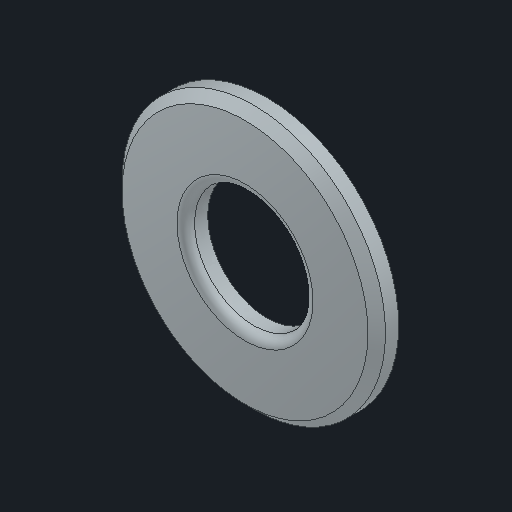
# Autodesk Inventor part: Arruela Lisa DIN 125 - B2,5 - 300 HV
Saved by Autodesk Inventor 2026.1 (Build 301233000, 233)
## iProperties
Created: 2025-07-13
Part Number: Arruela Lisa DIN 125 - B2,5 - 300 HV
Material: Aço, carbono
Document SubType Name: Modeling
Designer: Cliente
Mass: 0.0850199 g
Surface Area: 0.557927 cm^2
Volume: 0.0108306 cm^3
Density: 7.85 g/cm^3
Appearance: Zinco
Author: Cliente
Autodesk Inventor part; units mm, degrees
ref_plane "YZ Plane" through (0, 0, 0) normal (1, 0, 0) x (0, 1, 0)
ref_plane "XZ Plane" through (0, 0, 0) normal (0, 1, 0) x (-1, 0, 0)
ref_plane "XY Plane" through (0, 0, 0) normal (0, 0, 1) x (1, 0, 0)
sketch "Esboço1" plane through (0, 0, 0) normal (0, 1, 0) x (-1, 0, 0)
  line L0 (0, 0) -> (1.35, 0)
  line L1 (0, 1.0374) -> (0, 0)
  line L2 (1.35, 0) -> (1.35, 0.3)
  line L3 (0, 0) -> (3, 0)
  line L4 (3, 0) -> (3, 0.3)
  line L5 (2.8, 0.5) -> (1.55, 0.5)
  line L6 (3, 0.3) -> (2.8, 0.5)
  arc A0 (1.55, 0.5) -> (1.35, 0.3) centre (1.55, 0.3) ccw
  point P0 (1.35, 0.5)
  point P1 (3, 0.5)
  point P2 (1.35, 0.5)
  dimension "d0" = 1.35
  dimension "d2" = 0.5
  dimension "d3" = 3
  dimension "d4" = 0.2
  dimension "d5" = 0.2
  dimension "d9" = 0.2
  constraints: 14 end point, 6 point on line, 3 vertical, 2 horizontal, 2 point on circle, 2 tangent, 1 centre point, 1 perpendicular
  measures "d0" distance of L0.start L0.end
  measures "d2" distance of L0.end point (1.35, 0.5)
  measures "d3" distance of L0.start L3.end
  measures "d4" distance of L4.end point (3, 0.5)
  measures "d5" distance of L5.start point (3, 0.5)
  measures "d9" radius of A0
revolve "Revolução1" add sketch "Esboço1" angle 360 about axis through (0, 0, 1.0374) along (0, 0, -1)
equation "\"d5\" = d4"
